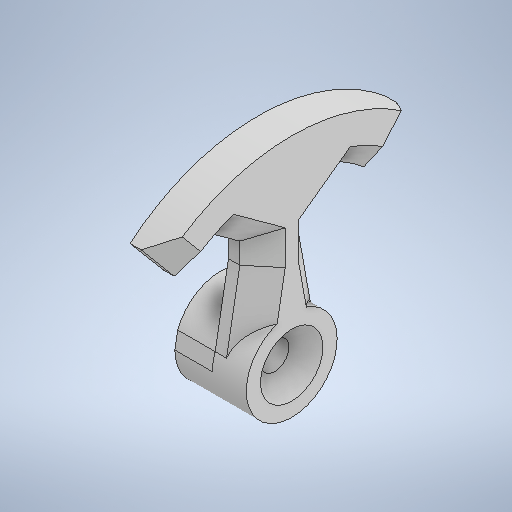
# Autodesk Inventor part: kachalka
Saved by Autodesk Inventor 2025 (Build 290162000, 162)
## iProperties
Created: 2026-11-03
Part Number: kachalka
Material: Типовые
Document SubType Name: Modeling
Designer: Leva
Density: 1 g/cm^3
Appearance: По умолчанию
Author: Leva
Autodesk Inventor part; units mm, degrees
ref_plane "YZ Plane" through (0, 0, 0) normal (1, 0, 0) x (0, 1, 0)
ref_plane "XZ Plane" through (0, 0, 0) normal (0, 1, 0) x (-1, 0, 0)
ref_plane "XY Plane" through (0, 0, 0) normal (0, 0, 1) x (1, 0, 0)
sketch "Эскиз2" plane through (0, 0, 0) normal (1, 0, 0) x (0, 1, 0)
  circle A0 centre (0, 0) radius 17.5
  line L0 (0, 0) -> (13.4058, -11.2488)
  line L1 (0, 0) -> (17.5, 0) construction
  line L2 (0, 0) -> (13.4058, 11.2488)
  circle A1 centre (0, 0) radius 13
  circle A2 centre (0, 0) radius 4
  line L3 (3.0642, 2.5712) -> (12.7432, 2.5712)
  line L4 (3.0642, -2.5712) -> (12.7432, -2.5712)
  circle A3 centre (0, 0) radius 2
  circle A4 centre (0, 0) radius 1.25
  line L5 (0, 0) -> (0, 4) construction
  line L6 (0, 4) -> (7.9037, 2.5712)
  line L7 (0, -4) -> (7.9037, -2.5712)
  line L8 (12.7432, 2.5712) -> (17.3101, 2.5712)
  point P0 (9.9586, -8.3562)
  point P1 (13.4058, 11.2488)
  point P2 (9.9586, 8.3562)
  point P3 (1.4005, 3.7468)
  point P4 (0, -4)
  point P5 (1.4005, -3.7468)
  point P6 (7.9037, -2.5712)
  dimension "d3" = 35
  dimension "d4" = 40
  dimension "d6" = 26
  dimension "d7" = 8
  dimension "d8" = 4
  dimension "d18" = 2.5
  constraints: 18 end point, 7 point on circle, 5 centre point, 5 coincident, 3 point on line, 3 symmetric about line, 2 horizontal, 1 equal length, 1 midpoint, 1 parallel, 1 vertical
  measures "d3" diameter of A0
  measures "d4" angle of L0 L1
  measures "d6" diameter of A1
  measures "d7" diameter of A2
  measures "d8" diameter of A3
  measures "d18" diameter of A4
extrude "Выдавливание1" add sketch "Эскиз2" along normal blind 3.3 contours A2 L0 A3 L2 | L2 A3 L0 A2 L7 L6
extrude "Выдавливание2" add sketch "Эскиз2" along normal blind 3 from surface at 3.3 contours A0 L0 A1 L8 | L8 A1 L2 A0 | A1 L4 A2 L3 | L3 L2 L6 | L7 A2 L0 | L0 L4 L7 | L2 A2 L6 | A2 L0 A3 L2 | L2 A3 L0 A2 L7 L6 | A2 L7 | L6 A2 | A3 L0 A4 L2 | L2 A4 L0 A3
chamfer "Фаска2" distance 3 angle 45 2 edges at (4.8, 12.7432, -2.5712) (4.8, 12.7432, 2.5712)
chamfer "Фаска3" distance 1.5 angle 45 1 edges at (6.3, -1.25, 0)
chamfer "Фаска4" distance 2 angle 45 10 edges at (6.3, 4.6521, 3.159) (6.3, 8.8234, 2.5712) (6.3, 4.6521, -3.159) (6.3, 8.8234, -2.5712) (6.3, 10.7789, -3.9975) (6.3, 10.9848, -6.9522) (6.3, 11.6822, -9.8025) (6.3, 10.7789, 3.9975) (6.3, 10.9848, 6.9522) (6.3, 11.6822, 9.8025)
